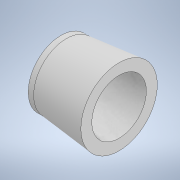
# Autodesk Inventor part: bagheeta
Saved by Autodesk Inventor 2022.6 (Build 266554000, 554)
## iProperties
Created: 2026-03-16
Part Number: bagheeta
Material: Generic
Document SubType Name: Modeling
Designer: Dragos Macovei
Density: 1 g/cm^3
Appearance: Default
Author: Dragos Macovei
Autodesk Inventor part; units mm, degrees
ref_plane "YZ Plane" through (0, 0, 0) normal (1, 0, 0) x (0, 1, 0)
ref_plane "XZ Plane" through (0, 0, 0) normal (0, 1, 0) x (-1, 0, 0)
ref_plane "XY Plane" through (0, 0, 0) normal (0, 0, 1) x (1, 0, 0)
sketch "Sketch1" plane through (0, 0, 0) normal (0, 1, 0) x (-1, 0, 0)
  line L0 (9.6571, 0) -> (9.6571, -4)
  line L1 (9.6571, -4) -> (9.6571, -6)
  line L2 (0, 0) -> (0, -5)
  line L3 (0, -5) -> (0, -7)
  line L4 (0, -7) -> (9.6571, -6)
  line L5 (9.6571, -4) -> (0, -5)
  line L6 (9.6571, 0) -> (0, 0)
  dimension "d2" = 4
  dimension "d3" = 2
  dimension "d4" = 5
  dimension "d5" = 2
  constraints: 14 end point, 2 point on line, 2 vertical, 1 horizontal
  measures "d2" distance of L0.start L0.end
  measures "d3" distance of L0.end L1.end
  measures "d4" distance of L2.start L2.end
  measures "d5" distance of L2.end L3.end
revolve "Revolution1" add sketch "Sketch1" angle 360 about axis through (-9.6571, 0, 0) along (1, 0, 0) contours L1 L4 L3 L5
sketch "Sketch2" plane through (-9.6571, 0, 0) normal (-1, 0, 0) x (0, 0, 1)
  circle A0 centre (0, 0) radius 5 projected
  circle A1 centre (0, 0) radius 4 projected
  circle A2 centre (0, 0) radius 6 projected
  circle A3 centre (0, 0) radius 6
  constraints: 1 centre point, 1 coincident, 1 concentric
extrude "Extrusion1" add sketch "Sketch2" along normal blind 1 contours A0 | A1 | A2
body "Solid1"
